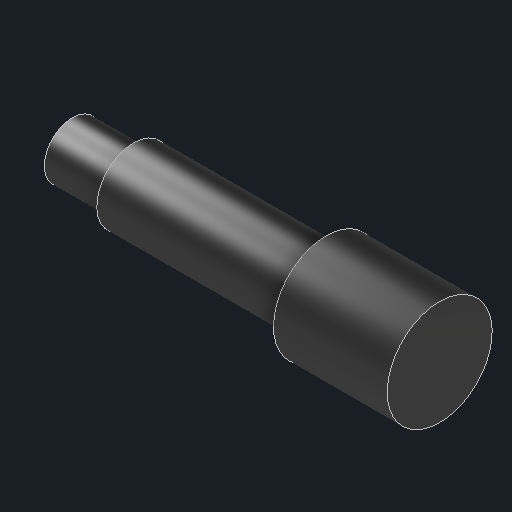
# Autodesk Inventor part: c8n_finder_9x50
Saved by Autodesk Inventor 2027.1 (Build 311270010, 270A)
## iProperties
Created: 2026-11-04
Part Number: c8n_finder_9x50
Material: Generic
Description: 9x50 finder (photo: finder on a bracket near the front)
Document SubType Name: Modeling
Designer: Claude (from photos)
Density: 1 g/cm^3
Appearance: Glossy - Black
Author: alexg
Autodesk Inventor part; units mm, degrees
ref_plane "Work Plane1" through (705, 0, 0) normal (1, 0, 0) x (0, 1, 0)
sketch "Eyepiece sketch" plane through (705, 0, 0) normal (1, 0, 0) x (0, 1, 0)
  circle A0 centre (180, 0) radius 16
  constraints: 1 centre point
extrude "Eyepiece" add sketch "Eyepiece sketch" along normal blind 40
ref_plane "Work Plane2" through (740, 0, 0) normal (1, 0, 0) x (0, 1, 0)
sketch "Main tube sketch" plane through (740, 0, 0) normal (1, 0, 0) x (0, 1, 0)
  circle A0 centre (180, 0) radius 21
  constraints: 1 centre point
extrude "Main tube" add sketch "Main tube sketch" along normal blind 110
ref_plane "Work Plane3" through (850, 0, 0) normal (1, 0, 0) x (0, 1, 0)
sketch "Objective cell 50 mm sketch" plane through (850, 0, 0) normal (1, 0, 0) x (0, 1, 0)
  circle A0 centre (180, 0) radius 30
  constraints: 1 centre point
extrude "Objective cell 50 mm" add sketch "Objective cell 50 mm sketch" along normal blind 65
body "Solid1"
